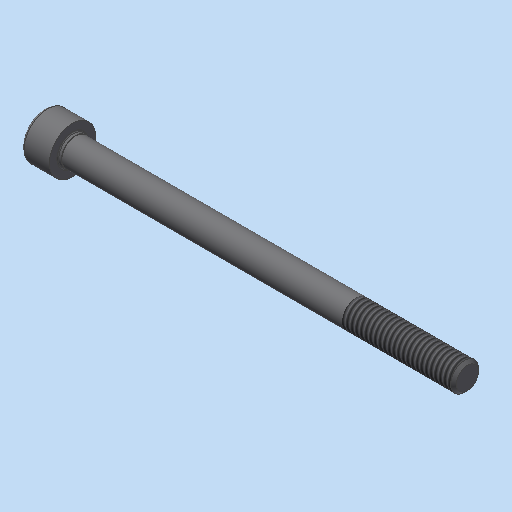
# Autodesk Inventor part: Zylinderschraube_ISO_4762___M6x85
Saved by Autodesk Inventor 2023.3 (Build 273359000, 359)
## iProperties
Category: PARTsolutions
Created: 2007-05-03
Part Number: Zylinderschraube_ISO_4762___M6x85
Catalog Web Link: www.cadenas.de
Description: =<RBPARTNOTITLE2>
Vendor: Norm8
Document SubType Name: Modellieren
Standard: M6x85
Designer: gma9ba
Manufacturer: CADENAS GmbH
Standards Organization: ISO 4762
Material: xStahl_AnP_Dummymaterial
Density: 7.85 g/cm^3
Mass: 21.825 g
Surface Area: 19.9303 cm^2
Volume: 2.78025 cm^3
Appearance: Stahl - normal AnP
RBPARTNOTITLE1: Hexagon socket head cap screws
RBPARTMADEOF: ISO 4762 - M6x85 - 8.8 verzinkt
RBPARTNOTITLE2: Zylinderschrauben mit Innensechskant
CNS_NB: Zylinderschraube ISO 4762 - M6x85
CNS_NN: ISO 4762
CNS_NT: Zylinderschrauben mit Innensechskant
CNS_NBSYN: Zylinderschraube ISO 4762 - $NENN.
CNS_LINA: Zylinderschraube ISO 4762 - M6x85
CNS_D: 6.000
CNS_D3: 4.773
CNS_P: 1.000
CNS_L: 85.000
CNS_S: 5.000
CNS_HM: 24.000
CNS_DK: 10.000
CNS_DA: 6.800
CNS_DS: 6.000
CNS_E: 5.720
CNS_K: 6.000
CNS_R: 0.250
CNS_T: 3.000
CNS_V: 0.600
CNS_DW: 9.380
CNS_W: 2.300
CNS_LF: 0.680
CNS_LG: 61.000
CNS_FORM: 0.000
CNS_NENN: M6x85
CNS_KT: DUMMY
CNS_LINA2: Zylinderschraube ISO 4762 - M6x85
CNS_COMPANY: CADENAS GmbH
PSOL_IDENT_0: {\\ba0cad02\tef2_cad\_bibliothek\23d-libs\norm\din_en_iso\schrauben\zylinderschrauben\din_en_iso_476
PSOL_IDENT_1: 2.prj},210 {M=Nenngewinde},{VTYP=3D},{NB=Zylinderschraube ISO 4762 - M6x85},{LINA=Zylinderschraube I
PSOL_IDENT_2: SO 4762 - M6x85},{NN=ISO 4762},{DATE=3.5.2007},{GEOMDATE=26.11.2003},{VERSION=v1},{LINEID=2240},{LIN
PSOL_IDENT_3: ESUBID=-1},{WBVAR=}  {NB=Zylinderschraube ISO 4762 - M6x85},{LINA=Zylinderschraube ISO 4762 - M6x85}
PSOL_IDENT_4: ,{KT=DUMMY},{IDNR=},{D=6.000},{D3=4.773},{P=1.000},{L=85.000},{S=5.000},{HM=24.000},{DK=10.000},{DA=
PSOL_IDENT_5: 6.800},{DS=6.000},{E=5.720},{K=6.000},{R=0.250},{T=3.000},{V=0.600},{DW=9.380},{W=2.300},{LF=0.680},
PSOL_IDENT_6: {LG=61.000},{FORM=0.000},{NENN=M6x85}
Norm: ISO 4762
Size: M6x85
AnP_Kategorie: 4
RBDRAWINGMISSINGSPEC: --
GAIN_REFID: 20__Zylinderschraube_ISO_4762___M6x85:E6D76
Title: Zylinderschraube ISO 4762 - M6x85
Author: Cadenas PARTsolutions
Keywords: =<RBPARTMADEOF>
Comments: =<RBSURFACE2>
Revision Number: 01
Autodesk Inventor part; units mm, degrees
sketch "Sketch_1" plane through (0, 0, 0) normal (0, 1, 0) x (-1, 0, 0)
  line L0 (-88, 0) -> (9, 0)
  line L1 (0.8566, 0) -> (2.3, -2.5)
  line L2 (2.3, -2.5) -> (5.64, -2.5)
  line L3 (5.64, -2.5) -> (6, -2.86)
  line L4 (6, -2.86) -> (6, -4.4)
  arc A0 (5.4, -5) -> (6, -4.4) centre (5.4, -4.4) ccw
  line L5 (5.4, -5) -> (0, -5)
  line L6 (0, -5) -> (0, -3.4)
  arc A1 (0, -3.4) -> (-0.1677, -3.1639) centre (-0.25, -3.4) ccw
  line L7 (-0.1677, -3.1639) -> (-0.5977, -3.0139)
  arc A2 (-0.5977, -3.0139) -> (-0.68, -3) centre (-0.68, -3.25) ccw
  line L8 (-0.68, -3) -> (-84.3865, -3)
  line L9 (-84.3865, -3) -> (-85, -2.3865)
  line L10 (-85, -2.3865) -> (-85, 0)
  line L11 (-85, 0) -> (0.8566, 0)
  constraints: 24 end point, 6 point on circle, 3 centre point
revolve "Drehung1" add sketch "Sketch_1" angle 360 about axis through (88, 0, 0) along (1, 0, 0)
thread "Gewinde1" size "M6x1" class "6g" standard "ISO Metrisches Profil" length 23.3865
sketch "Skizze_1" plane through (-2.3, 0, 0) normal (1, 0, 0) x (0, 0, -1)
  line L0 (-2.5, 1.4434) -> (-2.5, -1.4434)
  line L1 (-2.5, -1.4434) -> (0, -2.8868)
  line L2 (0, -2.8868) -> (2.5, -1.4434)
  line L3 (2.5, -1.4434) -> (2.5, 1.4434)
  line L4 (2.5, 1.4434) -> (0, 2.8868)
  line L5 (0, 2.8868) -> (-2.5, 1.4434)
  constraints: 12 end point
extrude "Extrusion1" cut sketch "Skizze_1" against normal blind 6
ref_plane "IP1_XY" through (0, 0, 0) normal (1, 0, 0) x (0, 0, -1)
ref_plane "IP1_YZ" through (0, 0, 0) normal (0, 0, -1) x (0, 1, 0)
ref_plane "IP1_ZX" through (0, 0, 0) normal (0, 1, 0) x (1, 0, 0)
ref_plane "IP3_XY" through (85, 0, 0) normal (1, 0, 0) x (0, 0, -1)
ref_plane "IP3_YZ" through (85, 0, 0) normal (0, 0, -1) x (0, 1, 0)
ref_plane "IP3_ZX" through (85, 0, 0) normal (0, 1, 0) x (1, 0, 0)
ref_plane "IP2_XY" through (-6, 0, 0) normal (1, 0, 0) x (0, 0, -1)
ref_plane "IP2_YZ" through (-6, 0, 0) normal (0, 0, -1) x (0, 1, 0)
ref_plane "IP2_ZX" through (-6, 0, 0) normal (0, 1, 0) x (1, 0, 0)
